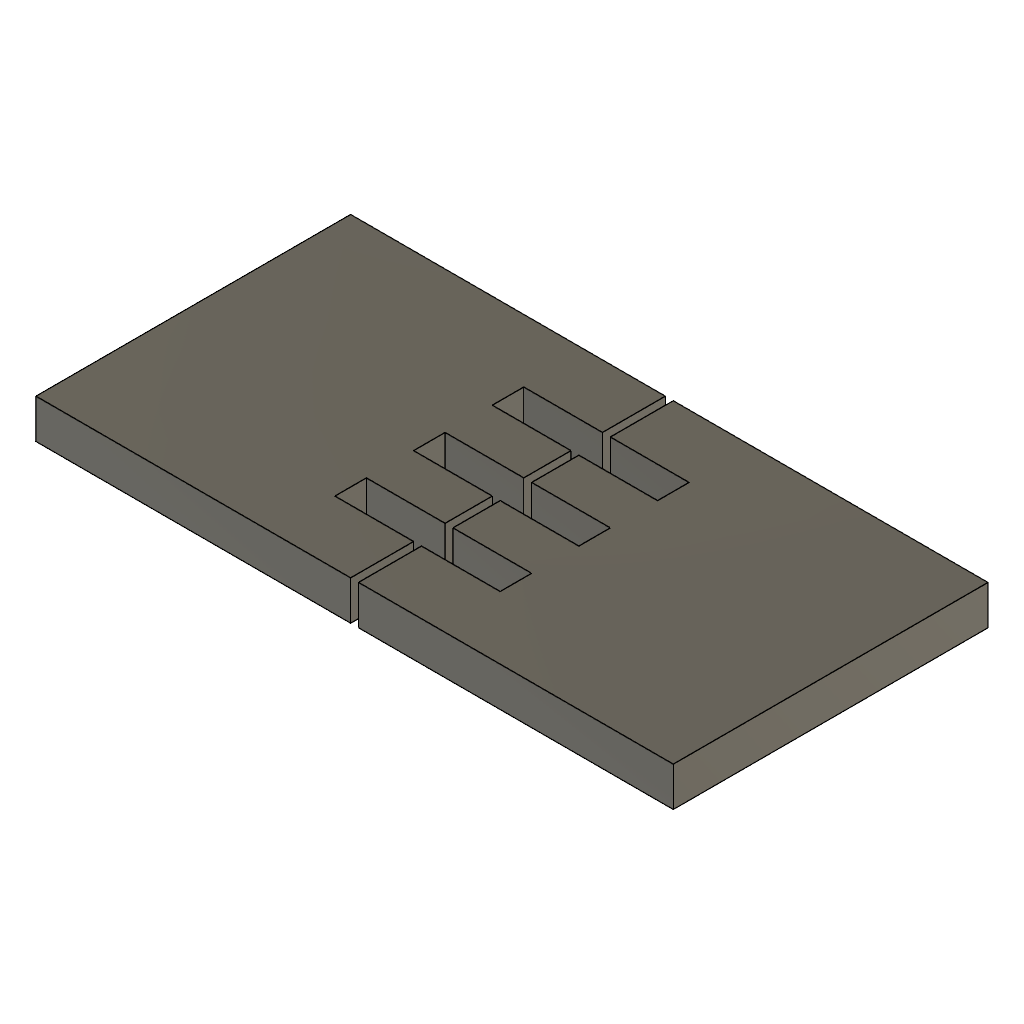
two_target_pattern (Autodesk Fusion 360 design; units mm, degrees)
Autodesk Fusion 360 part; units mm, degrees
sketch "Sketch1" plane through (0, 0, 0) normal (0, 0, 1) x (1, 0, 0)
  line L0 (0, 0) -> (40, 0)
  line L1 (40, 0) -> (40, 40)
  line L2 (40, 40) -> (0, 40)
  line L3 (0, 40) -> (0, 0)
extrude "Extrude1" add sketch "Sketch1" along normal blind 5 makes body 1
sketch "Sketch2" plane through (0, 0, 0) normal (0, 0, 1) x (1, 0, 0)
  line L0 (41, 0) -> (81, 0)
  line L1 (81, 0) -> (81, 40)
  line L2 (81, 40) -> (41, 40)
  line L3 (41, 40) -> (41, 0)
extrude "Extrude2" add sketch "Sketch2" along normal blind 5 separate body makes body 2
ref_plane "WorkPlane1" through (0, 0, 5) normal (0, 0, 1) x (1, 0, 0)
sketch "SlotSketch" plane through (0, 0, 5) normal (0, 0, 1) x (1, 0, 0)
  line L0 (30, 8) -> (51, 8)
  line L1 (51, 8) -> (51, 12)
  line L2 (51, 12) -> (30, 12)
  line L3 (30, 12) -> (30, 8)
extrude "Extrude3" cut sketch "SlotSketch" against normal blind 5 bodies 1 2
pattern_linear "R-Pattern1" count 3 spacing 10 along (0, 1, 0) of "Extrude3"
